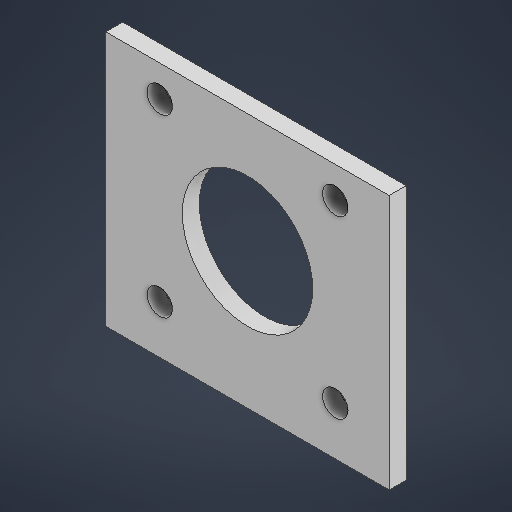
# Autodesk Inventor part: bracket
Saved by Autodesk Inventor 2027.1 (Build 311270010, 270A)
## iProperties
Created: 2026-10-03
Part Number: bracket
Material: Generic
Document SubType Name: Modeling
Designer: khaar
Density: 1 g/cm^3
Appearance: Default
Author: khaar
Autodesk Inventor part; units mm, degrees
ref_plane "YZ Plane" through (0, 0, 0) normal (1, 0, 0) x (0, 1, 0)
ref_plane "XZ Plane" through (0, 0, 0) normal (0, 1, 0) x (-1, 0, 0)
ref_plane "XY Plane" through (0, 0, 0) normal (0, 0, 1) x (1, 0, 0)
sketch "Sketch2" plane through (0, 0, 0) normal (0, 0, 1) x (1, 0, 0)
  line L0 (-25, 22.5) -> (25, 22.5)
  line L1 (25, 22.5) -> (25, -22.5)
  line L2 (25, -22.5) -> (-25, -22.5)
  line L3 (-25, -22.5) -> (-25, 22.5)
  line L4 (-25, 22.5) -> (25, -22.5) construction
  line L5 (25, 22.5) -> (-25, -22.5) construction
  point P0 (0, 0)
  dimension "d12" = 45
  dimension "d27" = 50
  constraints: 12 end point, 2 midpoint, 2 parallel, 1 horizontal, 1 perpendicular
  measures "d12" distance of L0.end L1.end
  measures "d27" distance of L0.start L0.end
extrude "Extrusion2" add sketch "Sketch2" along normal blind 3
sketch "Sketch10" plane through (0, 0, 3) normal (0, 0, 1) x (1, 0, 0)
  circle A0 centre (0, 1.5) radius 11.5
  line L0 (25, 22.5) -> (-25, 22.5) projected
  circle A1 centre (0, 1.5) radius 21.9 construction
  line L1 (0, 23.4) -> (0, 1.5) construction
  line L2 (0, 1.5) -> (15.4856, 16.9856) construction
  circle A2 centre (15.4856, 16.9856) radius 2.25
  line L3 (0, 1.5) -> (-15.4856, 16.9856) construction
  circle A3 centre (-15.4856, 16.9856) radius 2.25
  line L4 (0, 1.5) -> (-15.4856, -13.9856) construction
  circle A4 centre (-15.4856, -13.9856) radius 2.25
  line L5 (0, 1.5) -> (15.4856, -13.9856) construction
  circle A5 centre (15.4856, -13.9856) radius 2.25
  point P0 (0, 0)
  dimension "d45" = 23
  dimension "d46" = 21
  dimension "d47" = 43.8
  dimension "d48" = 45
  dimension "d49" = 4.5
  dimension "d52" = 360
  constraints: 10 end point, 7 coincident, 6 centre point, 2 point on circle, 1 vertical, 19 other
  measures "d45" diameter of A0
  measures "d46" distance from line of A0.centre L0
  measures "d47" diameter of A1
  measures "d48" angle of L1 L2
  measures "d49" diameter of A2
extrude "Extrusion7" cut sketch "Sketch10" against normal blind 3
body "Solid2"
